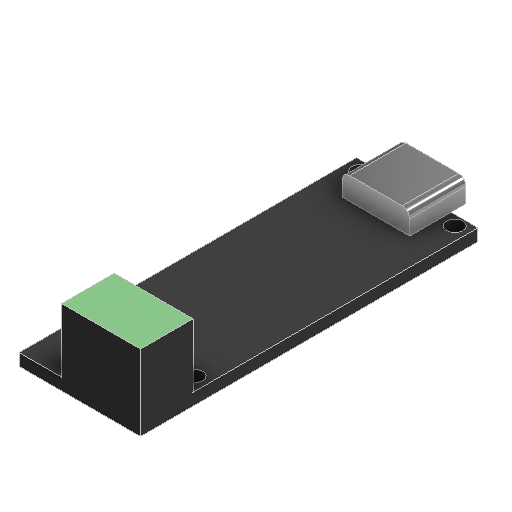
# Autodesk Inventor part: COTS_MKS_Canable_2_0
Saved by Autodesk Inventor 2027 (Build 310192060, 192F)
## iProperties
Created: 2026-01-18
Part Number: COTS_MKS_Canable_2_0
Material: Generic
Document SubType Name: Modeling
Designer: Andrzej
Density: 1 g/cm^3
Appearance: Rubber - Black
Author: Andrzej
Autodesk Inventor part; units mm, degrees
ref_plane "YZ Plane" through (0, 0, 0) normal (1, 0, 0) x (0, 1, 0)
ref_plane "XZ Plane" through (0, 0, 0) normal (0, 1, 0) x (-1, 0, 0)
ref_plane "XY Plane" through (0, 0, 0) normal (0, 0, 1) x (1, 0, 0)
sketch "Sketch1" plane through (0, 0, 0) normal (0, 1, 0) x (-1, 0, 0)
  line L0 (8.1, 22.5) -> (-8.1, 22.5)
  line L1 (-8.1, 22.5) -> (-8.1, -22.5)
  line L2 (-8.1, -22.5) -> (8.1, -22.5)
  line L3 (8.1, -22.5) -> (8.1, 22.5)
  point P0 (0, 0)
  point P1 (6.3, -21.2)
  point P2 (6.3, 13.5)
  point P3 (-6.3, 13.5)
  point P4 (-6.3, -21.2)
  dimension "d0" = 45
  dimension "d1" = 16.2
  dimension "d2" = 8.1
  dimension "d3" = 22.5
  dimension "d27" = 12.6
  dimension "d28" = 1.8
  dimension "d29" = 9
  dimension "d30" = 43.7
  constraints: 8 end point, 2 horizontal alignment, 2 parallel, 2 vertical alignment, 1 horizontal, 1 perpendicular
  measures "d0" distance of L2.end L0.start
  measures "d1" distance of L0.start L0.end
  measures "d2" distance from line of point (0, 0) L3
  measures "d3" distance from line of L0 point (0, 0)
  measures "d27" distance of point (-6.3, -21.2) point (6.3, -21.2)
  measures "d28" distance from line of L3 point (6.3, -21.2)
  measures "d29" distance from line of point (-6.3, 13.5) L0
  measures "d30" distance from line of point (-6.3, -21.2) L0
extrude "Extrusion1" add sketch "Sketch1" along normal blind 1.6
sketch "Sketch2" plane through (0, 1.6, 0) normal (0, 1, 0) x (1, 0, 0)
  line L0 (8.1, -22.5) -> (8.1, 22.5) projected
  line L1 (8.1, -22.5) -> (-2.4, -22.5)
  line L2 (-2.4, -22.5) -> (-2.4, -15.5)
  line L3 (-2.4, -15.5) -> (8.1, -15.5)
  line L4 (8.1, -15.5) -> (8.1, -22.5)
  line L5 (8.1, -22.5) -> (8.1, 22.5) projected
  line L6 (8.1, 22.5) -> (-8.1, 22.5) projected
  line L7 (-8.1, 22.5) -> (-8.1, -22.5) projected
  line L8 (-8.1, -22.5) -> (8.1, -22.5) projected
  point P0 (0, 0)
  point P1 (8.1, -15)
  dimension "d18" = 10.5
  dimension "d19" = 7
  constraints: 8 end point, 2 parallel, 1 horizontal, 1 perpendicular
  measures "d18" distance of L2.end L3.end
  measures "d19" distance of L1.end L2.end
extrude "Extrusion2" add sketch "Sketch2" along normal blind 8.5 contours L1 L2 L3 L0
sketch "Sketch3" plane through (0, 1.6, 0) normal (0, 1, 0) x (1, 0, 0)
  line L0 (-4.5, 17) -> (4.5, 17)
  line L1 (4.5, 17) -> (4.5, 24.5)
  line L2 (4.5, 24.5) -> (-4.5, 24.5)
  line L3 (-4.5, 24.5) -> (-4.5, 17)
  line L4 (8.1, 22.5) -> (-8.1, 22.5) projected
  point P0 (0, 0)
  dimension "d20" = 9
  dimension "d21" = 7.5
  dimension "d22" = 4.5
  dimension "d38" = 2
  constraints: 8 end point, 2 parallel, 1 horizontal, 1 perpendicular
  measures "d20" distance of L2.end L1.end
  measures "d21" distance of L1.end L0.end
  measures "d22" distance from line of point (0, 0) L3
  measures "d38" distance between parallel lines of L4 L2
extrude "Extrusion3" add sketch "Sketch3" along normal blind 3
fillet "Fillet1" radius 1 2 edges at (4.5, 4.6, -20.75) (-4.5, 4.6, -20.75)
hole "Hole1" at (-6.3, 0, -21.2) at (-6.3, 0, 13.5) at (6.3, 0, 13.5) at (6.3, 0, -21.2) direction (0, 1, 0) diameter 2.2 end through all
equation "\"d2\" = 0.5 * d1"
equation "\"d3\" = 0.5 * d0"
equation "\"d28\" = -0.5 * d27 + 0.5 * d1"
equation "\"d22\" = 0.5 * d20"
body "Solid1"
